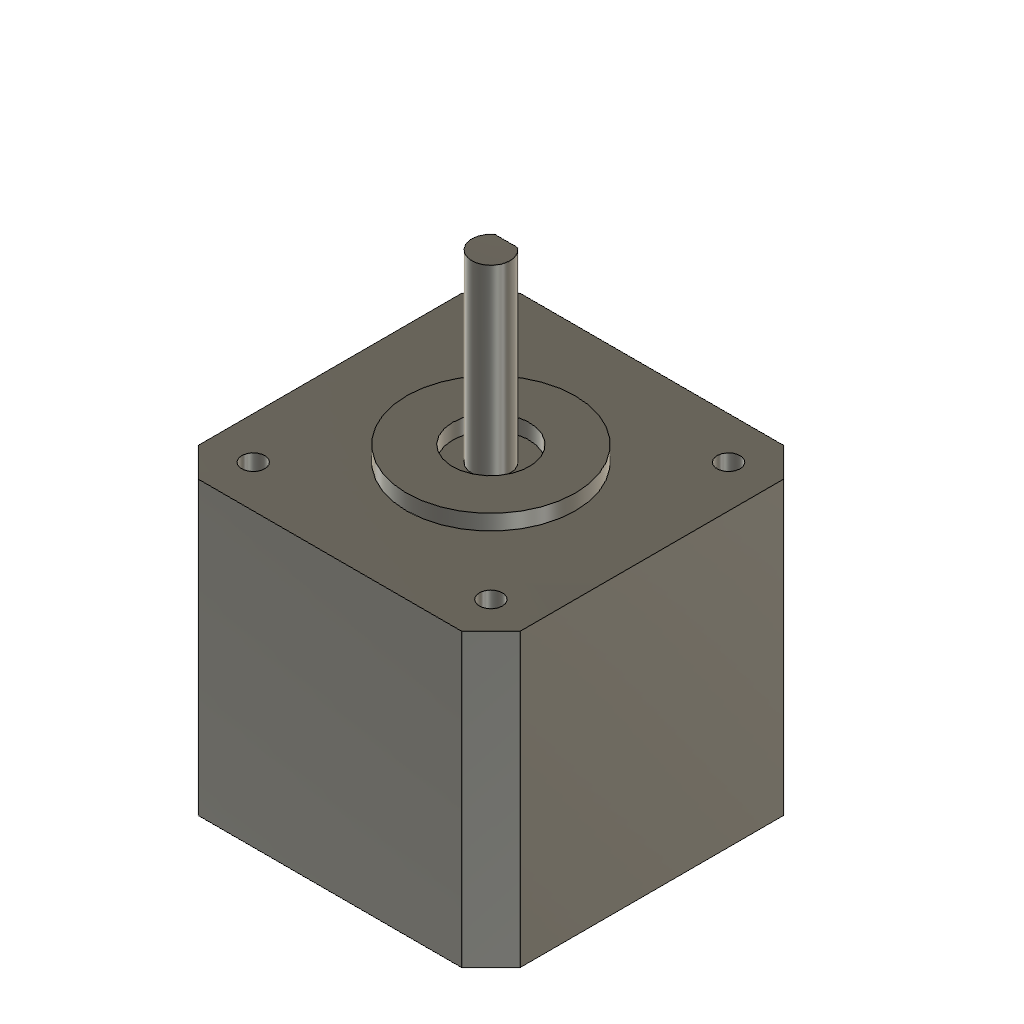
Nema17 (Autodesk Fusion 360 design; units mm, degrees)
part number: 2026-10-14-19-48-32-410
Autodesk Fusion 360 part; units mm, degrees
sketch "Sketch1" plane through (0, 0, 0) normal (0, 0, 1) x (1, 0, 0)
  circle A0 centre (0, 0) radius 2.5
  line L0 (-1.5, 2) -> (1.5, 2)
  line L1 (0, 0) -> (0, -2.5) construction
  line L2 (15.5, 15.5) -> (-15.5, 15.5) construction
  line L3 (-15.5, 15.5) -> (-15.5, -15.5) construction
  line L4 (-15.5, -15.5) -> (15.5, -15.5) construction
  line L5 (15.5, -15.5) -> (15.5, 15.5) construction
  line L6 (15.5, 15.5) -> (-15.5, -15.5)
  line L7 (-15.5, 15.5) -> (15.5, -15.5) construction
  circle A1 centre (-15.5, 15.5) radius 1.5
  circle A2 centre (-15.5, -15.5) radius 1.5
  circle A3 centre (15.5, -15.5) radius 1.5
  circle A4 centre (15.5, 15.5) radius 1.5
  line L8 (21, 21) -> (-21, 21)
  line L9 (-21, 21) -> (-21, -21)
  line L10 (-21, -21) -> (21, -21)
  line L11 (21, -21) -> (21, 21)
  line L12 (21, 21) -> (-21, -21) construction
  line L13 (-21, 21) -> (21, -21)
  circle A5 centre (0, 0) radius 11
  circle A6 centre (0, 0) radius 5
  line L14 (-21, 17.1838) -> (-17.1838, 21)
  line L15 (17.1838, -21) -> (21, -17.1838)
  line L16 (21, 17.1838) -> (17.1838, 21)
  line L17 (-17.1838, -21) -> (-21, -17.1838)
  dimension "d1" = 5
  dimension "d2" = 31
  dimension "d3" = 31
  dimension "d4" = 3
  dimension "d6" = 360
  dimension "d7" = 42
  dimension "d8" = 42
  dimension "d9" = 22
  dimension "d10" = 4.5
  dimension "d13" = 10
  dimension "d22" = 54
  constraint coincident A0.centre L1.start
  constraint coincident A0 L0.start
  constraint coincident A0 L0.end
  constraint horizontal L0
  constraint coincident A0 L1.end
  constraint vertical L1
  constraint horizontal L2
  constraint perpendicular L2 L3
  constraint parallel L2 L4
  constraint parallel L3 L5
  constraint coincident L6 A0.centre
  constraint coincident L7 A0.centre
  constraint coincident L2.end L3.start
  constraint horizontal L8
  constraint perpendicular L8 L9
  constraint parallel L8 L10
  constraint parallel L9 L11
  constraint coincident L12 A0.centre
  constraint coincident L13 A0.centre
  constraint coincident L9 L14.start
  constraint coincident L8 L14.end
  constraint perpendicular L13 L14
  constraint coincident L10 L15.start
  constraint coincident L11 L15.end
  constraint perpendicular L13 L15
  constraint symmetric L12 L14 L15
  constraint symmetric L1 L14.start L16.start
  constraint symmetric L1 L14.end L16.end
  constraint symmetric L1 L15.start L17.start
  constraint symmetric L1 L15.end L17.end
  measures "d1" diameter of A0
  measures "d2" distance of L3.end L4.end
  measures "d3" distance of L2.end L3.end
  measures "d4" diameter of A1
  measures "d7" distance of L9.end L10.end
  measures "d8" distance of L8.end L9.end
  measures "d9" diameter of A5
  measures "d10" distance of L0 L1.end
  measures "d13" diameter of A6
  measures "d22" distance of L14 L15
extrude "Extrude2" add sketch "Sketch1" along normal blind 2 contours L6 L13 A5 A6 | L6 L13 A5 A6 | L6 L13 A5 A6 | L6 L13 A5 A6
extrude "Extrude3" add sketch "Sketch1" against normal blind 38 contours A0 L0 | A0 L6 L13 A6 | A0 L0 L6 L13 | A0 L6 L13 A6 | A0 L6 L13 | A0 L6 L13 | A0 L6 L13 A6 | L6 L13 A5 A6 | L6 L13 A5 A6 | A0 L6 L13 | A0 L6 L13 A6 | L6 L13 A5 A6 | A1 A3 L8 L11 L13 A5 L14 L15 L16 | L6 L13 A5 A6 | A1 A3 L9 L10 L13 A5 L14 L15 L17 | A1 L13 | A1 L13 | A3 L13 | A3 L13 | A2 | A4
extrude "Extrude4" cut sketch "Sketch1" against normal blind 4.5 contours A1 L13 | A1 L13 | A3 L13 | A3 L13 | A2 | A4
extrude "Extrude5" add sketch "Sketch1" along normal blind 24 contours A0 L0 L6 L13 | A0 L6 L13 | A0 L6 L13 | A0 L6 L13
sketch "Sketch2" plane through (0, 21, 0) normal (0, 1, 0) x (-1, 0, 0)
  line L0 (17.1838, 0) -> (-17.1838, 0)
  line L1 (-17.1838, 0) -> (-17.1838, -38)
  line L2 (-17.1838, -38) -> (17.1838, -38)
  line L3 (17.1838, -38) -> (17.1838, 0)
  line L4 (0, 0) -> (0, -38)
  line L5 (-8.25, -38) -> (-8.25, -28)
  line L6 (-8.25, -28) -> (0, -28)
  line L7 (8.25, -28) -> (0, -28)
  line L8 (8.25, -38) -> (8.25, -28)
  dimension "d23" = 16.5
  dimension "d24" = 10
  constraint coincident L4.start origin
  constraint midpoint L2 L4.end
  constraint coincident L2 L5.start
  constraint perpendicular L2 L5
  constraint coincident L4 L6.end
  constraint perpendicular L4 L6
  constraint symmetric L4 L5.start L8.start
  constraint symmetric L4 L5.end L7.start
  constraint symmetric L4 L6.end L7.end
  measures "d23" distance of L5 L8
  measures "d24" distance of L2 L7
extrude "Extrude6" add sketch "Sketch2" along normal blind 5.5 contours L2 L4 L7 L8 | L2 L4 L5 L6
